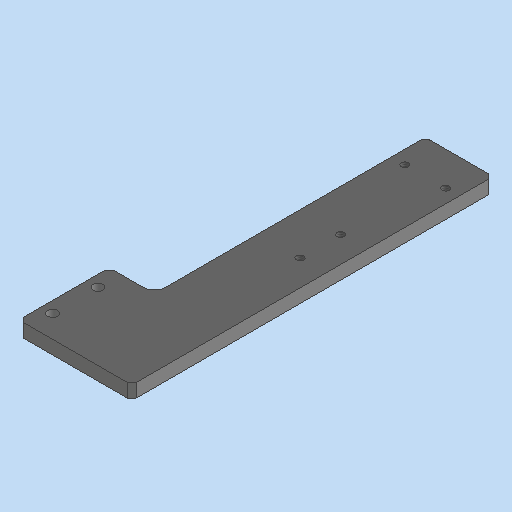
# Autodesk Inventor part: MM0948AN100_G01_209
Saved by Autodesk Inventor 2023.3 (Build 273359000, 359)
## iProperties
Created: 2024-02-27
Part Number: MM0948AN100_G01_209
Material: 1.4305 X8CrNiS18-9
Description: =<RBPARTNOTITLE2>
Document SubType Name: Modeling
Designer: RIC7AN
Mass: 262.147 g
Surface Area: 139.471 cm^2
Volume: 33.1832 cm^3
Density: 7.9 g/cm^3
Appearance: Stahl - rostfrei AnP
RBPARTMADEOF: 6 x 160 x 50 (FM)
RBDRAWINGMISSINGSPEC: --
AnP_Kategorie: 1
RBPARTNOTITLE2: Anfertigungsteil
RBSURFACE: --
RBPARTNOTITLE1: manufactured part
RBSURFACE2: --
AnP_Material: =<Material>
RBMATERIAL: =<Material>
RBMATNO: =<Part Number>
RBPARTNO: SIEHE MNR
MaxAbmaße: 6 x 160 x 50 (FM)
Author: RIC7AN
Keywords: =<RBPARTMADEOF>
Comments: =<RBSURFACE2>
Revision Number: 01
Autodesk Inventor part; units mm, degrees
ref_plane "YZ Plane" through (0, 0, 0) normal (1, 0, 0) x (0, 1, 0)
ref_plane "XZ Plane" through (0, 0, 0) normal (0, 1, 0) x (-1, 0, 0)
ref_plane "XY Plane" through (0, 0, 0) normal (0, 0, 1) x (1, 0, 0)
sketch "Skizze1" plane through (0, 0, 0) normal (0, 0, 1) x (1, 0, 0)
  line L0 (0, 0) -> (30, 0)
  line L1 (30, 0) -> (30, 160)
  line L2 (30, 160) -> (0, 160)
  line L3 (0, 160) -> (0, 0)
  line L4 (0, 0) -> (-20, 0)
  line L5 (-20, 0) -> (-20, 40)
  line L6 (-20, 40) -> (0, 40)
  line L7 (0, 40) -> (0, 0)
  line L8 (0, 192) -> (0, -32) projected
  line L9 (-30, 0) -> (40, 0) projected
  point P0 (0, 0)
  dimension "d0" = 40
  dimension "d1" = 20
  dimension "d2" = 30
  dimension "d3" = 160
  constraints: 16 end point, 4 parallel, 2 collinear, 2 horizontal, 2 perpendicular
  measures "d0" distance of L4.end L5.end
  measures "d1" distance of L5.end L6.end
  measures "d2" distance of L1.end L2.end
  measures "d3" distance of L0.end L1.end
extrude "Extrusion1" add sketch "Skizze1" along normal blind 6
sketch "Skizze2" plane through (0, 0, 6) normal (0, 0, 1) x (1, 0, 0)
  line L0 (-20, 0) -> (30, 0) projected
  point P0 (0, 0)
  point P1 (-15, 30)
  point P2 (-15, 10)
  dimension "d6" = 20
  dimension "d7" = 15
  dimension "d8" = 10
  constraints: 1 vertical alignment
  measures "d6" distance of point (-15, 10) point (-15, 30)
  measures "d7" horizontal distance of point (-15, 10) point (0, 0)
  measures "d8" distance from line of L0 point (-15, 10)
hole "Bohrung1" at (-15, 30, 6) at (-15, 10, 6) direction (0, 0, -1) diameter 4.5 end through all clearance for "Inbusschraube ISO 4762  versenkt" size "M4" standard "ISO"
sketch "Skizze3" plane through (0, 0, 6) normal (0, 0, 1) x (1, 0, 0)
  line L0 (30, 0) -> (30, 160) projected
  circle A0 centre (-15, 10) radius 2.25 projected
  line L1 (0, 160) -> (0, 40) projected
  point P0 (0, 0)
  point P1 (6, 145)
  point P2 (24, 145)
  point P3 (18.5, 104)
  point P4 (18.5, 86)
  dimension "d16" = 18
  dimension "d17" = 6
  dimension "d18" = 135
  dimension "d26" = 18
  dimension "d27" = 76
  dimension "d28" = 18.5
  constraints: 1 horizontal alignment, 1 vertical alignment
  measures "d16" distance of point (24, 145) point (6, 145)
  measures "d17" distance from line of L0 point (24, 145)
  measures "d18" vertical distance of A0.centre point (24, 145)
  measures "d26" distance of point (18.5, 86) point (18.5, 104)
  measures "d27" vertical distance of A0.centre point (18.5, 86)
  measures "d28" distance from line of point (18.5, 86) L1
hole "Bohrung2" at (6, 145, 6) at (24, 145, 6) at (18.5, 104, 6) at (18.5, 86, 6) direction (0, 0, -1) diameter 3.242 end through all thread size "M4x0.7" designation "M4" class "6H" standard "ISO Metric profile"
fillet "Rundung1" radius 5 1 edges at (0, 40, 3)
chamfer "Fase1" distance 2 angle 45 5 edges at (-20, 40, 3) (-20, 0, 3) (30, 0, 3) (0, 160, 3) (30, 160, 3)
